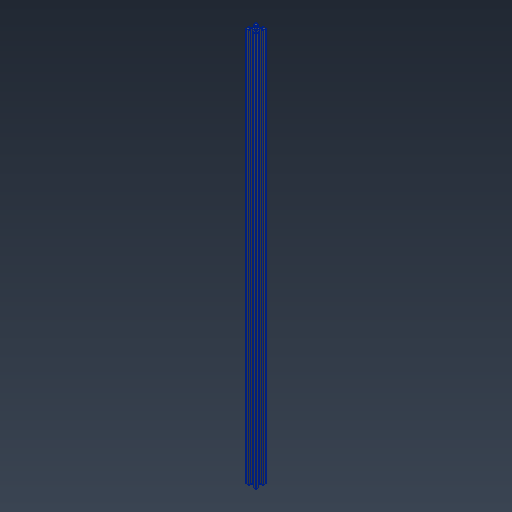
# Autodesk Inventor part: 2020Profile-800mm
Saved by Autodesk Inventor 2026.2 (Build 302298010, 298A)
## iProperties
Created: 2026-05-13
Part Number: 2020Profile-800mm
Material: 알루미늄 6061
Document SubType Name: Modeling
Designer: khw
Density: 2.7 g/cm^3
Appearance: 알루미늄 - 평지
Author: khw
Autodesk Inventor part; units mm, degrees
ref_plane "YZ Plane" through (0, 0, 0) normal (1, 0, 0) x (0, 1, 0)
ref_plane "XZ Plane" through (0, 0, 0) normal (0, 1, 0) x (-1, 0, 0)
ref_plane "XY Plane" through (0, 0, 0) normal (0, 0, 1) x (1, 0, 0)
sketch "스케치1" plane through (0, 0, 0) normal (0, 1, 0) x (-1, 0, 0)
  line L0 (-10, 10) -> (10, 10)
  line L1 (10, 10) -> (10, -10)
  line L2 (10, -10) -> (-10, -10)
  line L3 (-10, -10) -> (-10, 10)
  line L4 (-10, 10) -> (10, -10) construction
  line L5 (10, 10) -> (-10, -10) construction
  line L6 (10, 4.9) -> (5.1, 0) construction
  line L7 (5.1, 0) -> (10, -4.9) construction
  line L8 (8.2, 3.1) -> (8.2, 5.4993)
  line L9 (3.9007, 2.84) -> (3.9007, 0)
  line L10 (0, 0) -> (10, 0) construction
  line L11 (10, 4.9) -> (8.2, 3.1)
  line L12 (8.2, 5.4993) -> (6.56, 5.4993)
  line L13 (6.56, 5.4993) -> (3.9007, 2.84)
  circle A0 centre (0, 0) radius 2.1
  line L14 (8.2, -3.1) -> (8.2, -5.4993)
  line L15 (3.9007, -2.84) -> (3.9007, 0)
  line L16 (10, -4.9) -> (8.2, -3.1)
  line L17 (8.2, -5.4993) -> (6.56, -5.4993)
  line L18 (6.56, -5.4993) -> (3.9007, -2.84)
  line L19 (4.9, 10) -> (3.1, 8.2)
  line L20 (3.1, 8.2) -> (5.4993, 8.2)
  line L21 (5.4993, 6.56) -> (2.84, 3.9007)
  line L22 (0, 5.1) -> (4.9, 10) construction
  line L23 (-3.1, 8.2) -> (-5.4993, 8.2)
  line L24 (-4.9, 10) -> (0, 5.1) construction
  line L25 (-5.4993, 8.2) -> (-5.4993, 6.56)
  line L26 (0, 0) -> (0, 10) construction
  line L27 (-10, 10) -> (10, -10) construction
  line L28 (-5.4993, 6.56) -> (-2.84, 3.9007)
  line L29 (-4.9, 10) -> (-3.1, 8.2)
  line L30 (-2.84, 3.9007) -> (0, 3.9007)
  line L31 (2.84, 3.9007) -> (0, 3.9007)
  line L32 (5.4993, 8.2) -> (5.4993, 6.56)
  line L33 (-10, 4.9) -> (-8.2, 3.1)
  line L34 (-8.2, 3.1) -> (-8.2, 5.4993)
  line L35 (-6.56, 5.4993) -> (-3.9007, 2.84)
  line L36 (-5.1, 0) -> (-10, 4.9) construction
  line L37 (-8.2, -3.1) -> (-8.2, -5.4993)
  line L38 (-10, -4.9) -> (-5.1, 0) construction
  line L39 (-8.2, -5.4993) -> (-6.56, -5.4993)
  line L40 (0, 0) -> (-10, 0) construction
  line L41 (-10, -10) -> (10, 10) construction
  line L42 (-6.56, -5.4993) -> (-3.9007, -2.84)
  line L43 (-10, -4.9) -> (-8.2, -3.1)
  line L44 (-3.9007, -2.84) -> (-3.9007, 0)
  line L45 (-3.9007, 2.84) -> (-3.9007, 0)
  line L46 (-8.2, 5.4993) -> (-6.56, 5.4993)
  line L47 (-4.9, -10) -> (-3.1, -8.2)
  line L48 (-3.1, -8.2) -> (-5.4993, -8.2)
  line L49 (-5.4993, -6.56) -> (-2.84, -3.9007)
  line L50 (0, -5.1) -> (-4.9, -10) construction
  line L51 (3.1, -8.2) -> (5.4993, -8.2)
  line L52 (4.9, -10) -> (0, -5.1) construction
  line L53 (5.4993, -8.2) -> (5.4993, -6.56)
  line L54 (0, 0) -> (0, -10) construction
  line L55 (10, -10) -> (-10, 10) construction
  line L56 (5.4993, -6.56) -> (2.84, -3.9007)
  line L57 (4.9, -10) -> (3.1, -8.2)
  line L58 (2.84, -3.9007) -> (0, -3.9007)
  line L59 (-2.84, -3.9007) -> (0, -3.9007)
  line L60 (-5.4993, -8.2) -> (-5.4993, -6.56)
  point P0 (5.2303, 4.1697)
  point P1 (4.1697, 5.2303)
  dimension "d0" = 20
  dimension "d1" = 20
  dimension "d2" = 135
  dimension "d3" = 1.64
  dimension "d4" = 4.2
  dimension "d5" = 5.68
  dimension "d6" = 6.2
  dimension "d9" = 360
  dimension "d11" = 1.5
  dimension "d12" = 1.8
  constraints: 122 end point, 14 point on line, 5 midpoint, 5 symmetric about line, 4 parallel, 2 horizontal, 2 perpendicular, 1 centre point, 1 coincident, 1 collinear, 1 vertical, 125 other
  measures "d0" distance of L1.end L2.end
  measures "d1" distance of L0.end L1.end
  measures "d2" angle of L1 L6
  measures "d3" distance from line of L12.end L8
  measures "d4" diameter of A0
  measures "d5" distance of L15.start L9.start
  measures "d6" distance of L16.end L8.start
  measures "d11" distance of point (5.23, 4.17) point (4.17, 5.23)
  measures "d12" distance between parallel lines of L20 L0
extrude "돌출1" add sketch "스케치1" along normal blind 800 contours L0 L29 L23 L25 L28 L30 L31 L21 L32 L20 L19 L1 L11 L8 L12 L13 L9 L15 L18 L17 L14 L16 L2 L57 L51 L53 L56 L58 L59 L49 L60 L48 L47 L3 L43 L37 L39 L42 L44 L45 L35 L46 L34 L33
